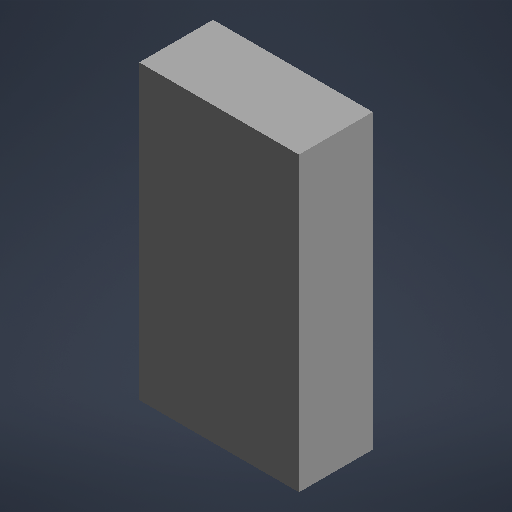
# Autodesk Inventor part: Proxy_ESP32
Saved by Autodesk Inventor 2027 (Build 310192060, 192F)
## iProperties
Part Number: Proxy_ESP32
Material: Genérico
Document SubType Name: Modelado
Designer: rodri
Appearance: Por defecto
Author: rodri
Autodesk Inventor part; units mm, degrees
ref_plane "Plano YZ" through (0, 0, 0) normal (1, 0, 0) x (0, 1, 0)
ref_plane "Plano XZ" through (0, 0, 0) normal (0, 1, 0) x (-1, 0, 0)
ref_plane "Plano de trabajo1" through (0, 0, -10.17) normal (0, 0, 1) x (1, 0, 0)
sketch "Boceto1" plane through (0, 0, -10.17) normal (0, 0, 1) x (1, 0, 0)
  line L0 (-2.44, -3.71) -> (26.57, -3.71)
  line L1 (26.57, -3.71) -> (26.57, 49.37)
  line L2 (26.57, 49.37) -> (-2.44, 49.37)
  line L3 (-2.44, 49.37) -> (-2.44, -3.71)
  constraints: 8 end point, 2 parallel, 1 horizontal, 1 perpendicular
extrude "Extrusión1" add sketch "Boceto1" along normal blind 13.42
